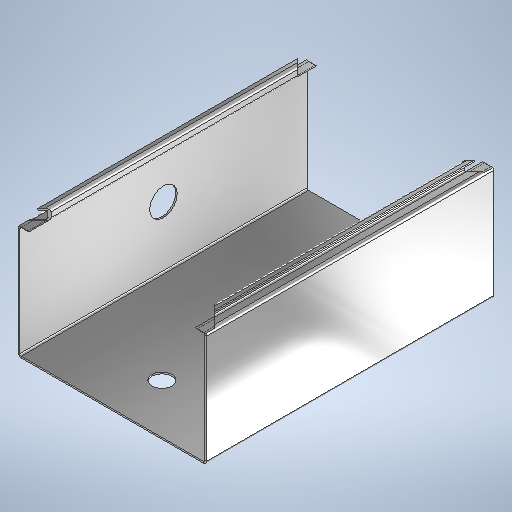
# Autodesk Inventor part: CHAPA 18 DE ACO INOX-304 - CAIXA
Saved by Autodesk Inventor 2025 (Build 290162000, 162)
## iProperties
Created: 2019-07-12
Part Number: CHAPA 18 DE ACO INOX-304 - CAIXA
Material: Aço inoxidável AISI 304
Document SubType Name: Chapa
Designer: CESAR
Density: 8 g/cm^3
Sheet Metal Rule: Default_mm
Appearance: Cromo - Acetinado
Flat Pattern Width: 22.9 cm
Flat Pattern Length: 36.3715 cm
Flat Pattern Area: 832.907 cm^2
Sheet Metal Width: 229,000 mm
Sheet Metal Length: 363,715 mm
Sheet Metal Area: 83290,664 mm^2
Mass: 3186.5 g
Surface Area: 6670.18 cm^2
Volume: 398.312 cm^3
Author: CESAR
Autodesk Inventor part; units mm, degrees
ref_plane "YZ Plane" through (0, 0, 0) normal (1, 0, 0) x (0, 1, 0)
ref_plane "XZ Plane" through (0, 0, 0) normal (0, 1, 0) x (-1, 0, 0)
ref_plane "XY Plane" through (0, 0, 0) normal (0, 0, 1) x (1, 0, 0)
sketch "Esboço1" plane through (0, 0, 0) normal (0, 0, 1) x (1, 0, 0)
  line L0 (75, -114.5) -> (-75, -114.5)
  line L1 (-75, -114.5) -> (-75, 114.5)
  line L2 (-75, 114.5) -> (75, 114.5)
  line L3 (75, 114.5) -> (75, -114.5)
  line L4 (75, -114.5) -> (-75, 114.5) construction
  line L5 (-75, -114.5) -> (75, 114.5) construction
  point P0 (0, 0)
  dimension "d0" = 150
  dimension "d1" = 229
  measures "d0" distance of L1.end L2.end
  measures "d1" distance of L0.end L1.end
extrude "Placa1" add sketch "Esboço1" along normal blind 1.2
sketch "Esboço2" plane through (-73.8, -114.5, 0) normal (-1, 0, 0) x (0, -1, 0)
  line L0 (-229, 0) -> (0, 0)
  line L1 (0, 0) -> (0, 91.2)
  line L2 (0, 91.2) -> (-229, 91.2)
  line L3 (-229, 91.2) -> (-229, 0)
  constraints: 4 end point, 4 other
edge flange "Flange1" height 90 angle 90 thickness 1.2 bend radius 1.2 thickness toward (-1, 0, 0) relief tear relief width 1.2 relief depth 0.6 corner gap 1.2 corner form 0 edges at (-75, 0, 1.2) (75, 0, 1.2) wall of the first edge with corners at (-73.8, 114.5, 0) (-73.8, -114.5, 0) (-73.8, -114.5, 91.2) (-73.8, 114.5, 91.2)
bend "Dobra1"
corner "Canto1"
sketch "Esboço3" plane through (-75, -114.5, 90) normal (0, 0, 1) x (1, 0, 0)
  line L0 (0, 229) -> (0, 0)
  line L1 (0, 0) -> (8.7, 0)
  line L2 (8.7, 0) -> (8.7, 229)
  line L3 (8.7, 229) -> (0, 229)
  constraints: 4 end point, 4 other
edge flange "Flange2" height 7.5 angle 90 thickness 1.2 bend radius 1.2 thickness toward (0, 0, 1) relief tear relief width 1.2 relief depth 0.6 corner gap 1.2 corner form 0 edges at (-73.8, 0, 91.2) (73.8, 0, 91.2) wall of the first edge with corners at (-75, 114.5, 90) (-75, -114.5, 90) (-66.3, -114.5, 90) (-66.3, 114.5, 90)
bend "Dobra2"
corner "Canto2"
sketch "Esboço4" plane through (-66.3, 114.5, 91.2) normal (1, 0, 0) x (0, 1, 0)
  line L0 (-229, 0) -> (0, 0)
  line L1 (0, 0) -> (0, 6.5)
  line L2 (0, 6.5) -> (-229, 6.5)
  line L3 (-229, 6.5) -> (-229, 0)
  constraints: 4 end point, 4 other
edge flange "Flange3" height 6.5 angle 90 thickness 1.2 bend radius 1.2 thickness toward (1, 0, 0) relief tear relief width 1.2 relief depth 0.6 corner gap 1.2 corner form 0 edges at (-66.3, 0, 91.2) (66.3, 0, 91.2) wall of the first edge with corners at (-66.3, -114.5, 91.2) (-66.3, 114.5, 91.2) (-66.3, 114.5, 97.7) (-66.3, -114.5, 97.7)
bend "Dobra3"
corner "Canto3"
sketch "Esboço5" plane through (66.3, -114.5, 97.7) normal (0, 0, 1) x (1, 0, 0)
  line L0 (0, 229) -> (0, 0)
  line L1 (0, 0) -> (4, 0)
  line L2 (4, 0) -> (4, 229)
  line L3 (4, 229) -> (0, 229)
  constraints: 4 end point, 4 other
edge flange "Flange4" height 4 angle 90 thickness 1.2 bend radius 1.2 thickness toward (0, 0, 1) relief tear relief width 1.2 relief depth 0.6 corner gap 1.2 corner form 0 edges at (66.3, 0, 97.7) (-66.3, 0, 97.7) wall of the first edge with corners at (66.3, 114.5, 97.7) (66.3, -114.5, 97.7) (70.3, -114.5, 97.7) (70.3, 114.5, 97.7)
bend "Dobra4"
corner "Canto4"
sketch "Esboço6" plane through (-70.3, -114.5, 98.9) normal (0, 0, 1) x (1, 0, 0)
  line L0 (5.2, 229) -> (5.2, 212.8)
  line L1 (5.2, 212.8) -> (-11, 229)
  line L2 (-11, 229) -> (5.2, 229)
  line L3 (5.2, 229) -> (5.2, 0) projected
  line L4 (5.2, 114.5) -> (-4.7, 114.5) construction
  line L5 (-4.7, 229) -> (-4.7, 0) projected
  line L6 (5.2, 0) -> (5.2, 16.2)
  line L7 (5.2, 16.2) -> (-11, 0)
  line L8 (-11, 0) -> (5.2, 0)
  line L9 (-2.3, 229) -> (142.9, 229) projected
  line L10 (70.3, 229) -> (70.3, 0) construction
  line L11 (142.9, 0) -> (-2.3, 0) projected
  line L12 (135.4, 229) -> (135.4, 212.8)
  line L13 (135.4, 212.8) -> (151.6, 229)
  line L14 (151.6, 229) -> (135.4, 229)
  line L15 (135.4, 0) -> (135.4, 16.2)
  line L16 (135.4, 16.2) -> (151.6, 0)
  line L17 (151.6, 0) -> (135.4, 0)
  point P0 (70.3, 114.5)
  point P1 (145.3, 229)
  point P2 (145.3, 0)
  dimension "d43" = 16.2
  constraints: 28 end point, 10 symmetric about line, 4 midpoint, 2 perpendicular, 1 horizontal
  measures "d43" distance of L0.start L1.end
extrude "Extrusão1" cut sketch "Esboço6" against normal blind 8.5 contours L0 L1 L5 L2 | L1 L2 L5 | L3 L8 L5 L7 | L5 L8 L7 | L9 L14 L13 L12 | L11 L15 L16 L17
sketch "Sketch10" plane through (0, 0, 0) normal (0, 0, -1) x (-1, 0, 0)
  point P0 (0, 0)
  point P1 (0, -75)
  dimension "d77" = 75
  constraints: 1 vertical alignment
  measures "d77" distance of point (0, -75) point (0, 0)
hole "Hole4" at (0, -75, 0) direction (0, 0, 1) diameter 16 depth 1.2 tip angle 118
sketch "Sketch11" plane through (-75, -114.5, 2.4) normal (-1, 0, 0) x (0, 0, 1)
  point P0 (-2.4, 114.5)
  point P1 (47.6, 114.5)
  dimension "d85" = 50
  constraints: 1 horizontal alignment
  measures "d85" distance of point (-2.4, 114.5) point (47.6, 114.5)
hole "Hole5" at (-75, 0, 50) direction (1, 0, 0) diameter 22 depth 1.2 tip angle 118
equation "\"d83\" = Espessura"
equation "\"d91\" = Espessura"
equation "\"d76\" = Espessura"
equation "\"d3\" = Largura_alívio_de_dobra"
equation "\"d4\" = Profundidade_alívio_de_dobra"
equation "\"d5\" = Remanescente_mínimo"
equation "\"d6\" = Raio_dobra"
equation "\"d9\" = Raio_dobra"
equation "\"d10\" = Tamanho_alívio_de_dobra"
equation "\"d11\" = TamanhoFolga"
equation "\"d12\" = Tamanho_de_raio_de_Jacobi"
equation "\"d13\" = Largura_alívio_de_dobra"
equation "\"d14\" = Profundidade_alívio_de_dobra"
equation "\"d15\" = Remanescente_mínimo"
equation "\"d16\" = Raio_dobra"
equation "\"d19\" = Raio_dobra"
equation "\"d20\" = Tamanho_alívio_de_dobra"
equation "\"d21\" = TamanhoFolga"
equation "\"d22\" = Tamanho_de_raio_de_Jacobi"
equation "\"d23\" = Largura_alívio_de_dobra"
equation "\"d24\" = Profundidade_alívio_de_dobra"
equation "\"d25\" = Remanescente_mínimo"
equation "\"d26\" = Raio_dobra"
equation "\"d29\" = Raio_dobra"
equation "\"d30\" = Tamanho_alívio_de_dobra"
equation "\"d31\" = TamanhoFolga"
equation "\"d32\" = Tamanho_de_raio_de_Jacobi"
equation "\"d33\" = Largura_alívio_de_dobra"
equation "\"d34\" = Profundidade_alívio_de_dobra"
equation "\"d35\" = Remanescente_mínimo"
equation "\"d36\" = Raio_dobra"
equation "\"d39\" = Raio_dobra"
equation "\"d40\" = Tamanho_alívio_de_dobra"
equation "\"d41\" = TamanhoFolga"
equation "\"d42\" = Tamanho_de_raio_de_Jacobi"
equation "\"Raio_dobra\" = Espessura"
equation "\"Largura_alívio_de_dobra\" = Espessura"
equation "\"Profundidade_alívio_de_dobra\" = 0.5 * Espessura"
equation "\"Tamanho_alívio_de_dobra\" = 4 * Espessura"
equation "\"Remanescente_mínimo\" = 2 * Espessura"
equation "\"Raiodetransição\" = Raio_dobra"
equation "\"Tamanho_de_raio_de_Jacobi\" = Raio_dobra"
equation "\"TamanhoFolga\" = Espessura"
equation "\"d2\" = Raio_dobra"
equation "\"Espessura\" = 1.2"
